Autodesk Fusion 360 part; units mm, degrees
(part 5 of 6)
sketch "Sketch1" plane through (0, 0, 0) normal (0, 1, 0) x (1, 0, 0)
  line L0 (-76.2, 57.15) -> (-76.2, -57.15) construction
  line L1 (76.2, -49.53) -> (76.2, 45.72) construction
  line L2 (-76.2, 57.15) -> (-38.1, 57.15) construction
  line L3 (-38.1, 57.15) -> (-38.1, 62.865) construction
  line L4 (-38.1, 62.865) -> (-19.05, 62.865) construction
  line L5 (-19.05, 62.865) -> (-19.05, 55.245) construction
  line L6 (-19.05, 55.245) -> (0, 55.245) construction
  line L7 (0, 55.245) -> (0, 45.72) construction
  line L8 (0, 45.72) -> (76.2, 45.72) construction
  line L9 (-76.2, -57.15) -> (-19.05, -57.15) construction
  line L10 (-19.05, -57.15) -> (-19.05, -59.055) construction
  line L11 (-19.05, -59.055) -> (0, -59.055) construction
  line L12 (0, -59.055) -> (0, -68.58) construction
  line L13 (0, -68.58) -> (57.15, -68.58) construction
  line L14 (57.15, -68.58) -> (57.15, -49.53) construction
  line L15 (57.15, -49.53) -> (76.2, -49.53) construction
  line L16 (-19.05, -59.055) -> (-19.05, -59.16) construction
  line L17 (-19.05, -59.16) -> (-19.115, -59.16) construction
  line L18 (-19.115, -59.16) -> (-19.2509, -58.6529) construction
  line L19 (-19.2509, -58.6529) -> (-18.7438, -58.517) construction
  line L20 (-18.7438, -58.517) -> (-37.1447, -63.4475) construction
  line L21 (-37.1447, -63.4475) -> (-32.2142, -81.8484) construction
  line L22 (-32.2142, -81.8484) -> (-13.8133, -76.9179) construction
  line L23 (-13.8133, -76.9179) -> (-18.7438, -58.517) construction
  line L24 (-37.1447, -63.4475) -> (-73.9464, -73.3085) construction
  line L25 (-73.9464, -73.3085) -> (-64.0854, -110.1103) construction
  line L26 (-64.0854, -110.1103) -> (-8.8828, -95.3188) construction
  line L27 (-8.8828, -95.3188) -> (-13.8133, -76.9179) construction
  line L28 (-76.2, 57.15) -> (-86.56, 57.15) construction
  line L29 (-86.56, 57.15) -> (-86.56, 59.625) construction
  line L30 (-76.2, -57.15) -> (-86.56, -57.15) construction
  line L31 (-86.56, -57.15) -> (-86.56, -59.625) construction
  line L32 (-73.9464, -73.3085) -> (-74.587, -70.9179) construction
  line L33 (-74.587, -70.9179) -> (-84.594, -73.5992) construction
  line L34 (-64.0854, -110.1103) -> (-63.4448, -112.501) construction
  line L35 (-63.4448, -112.501) -> (-73.4518, -115.1823) construction
  line L36 (-8.8828, -95.3188) -> (-8.2422, -97.7094) construction
  line L37 (-8.2422, -97.7094) -> (-5.8515, -97.0689) construction
  line L38 (0, -68.58) -> (-2.475, -68.58) construction
  line L39 (-2.475, -68.58) -> (-2.475, -71.055) construction
  line L40 (57.15, -68.58) -> (59.625, -68.58) construction
  line L41 (59.625, -68.58) -> (59.625, -71.055) construction
  line L42 (57.15, -49.53) -> (59.625, -49.53) construction
  line L43 (59.625, -49.53) -> (59.625, -52.005) construction
  line L44 (76.2, -49.53) -> (78.675, -49.53) construction
  line L45 (78.675, -49.53) -> (78.675, -52.005) construction
  line L46 (76.2, 45.72) -> (78.675, 45.72) construction
  line L47 (78.675, 45.72) -> (78.675, 48.195) construction
  line L48 (0, 45.72) -> (2.475, 45.72) construction
  line L49 (2.475, 45.72) -> (2.475, 48.195) construction
  line L50 (0, 55.245) -> (2.475, 55.245) construction
  line L51 (2.475, 55.245) -> (2.475, 57.72) construction
  line L52 (-19.05, 55.245) -> (-16.575, 55.245) construction
  line L53 (-16.575, 55.245) -> (-16.575, 57.72) construction
  line L54 (-19.05, 62.865) -> (-16.575, 62.865) construction
  line L55 (-16.575, 62.865) -> (-16.575, 65.34) construction
  line L56 (-38.1, 62.865) -> (-40.575, 62.865) construction
  line L57 (-40.575, 62.865) -> (-40.575, 65.34) construction
  line L58 (-38.1, 57.15) -> (-40.575, 57.15) construction
  line L59 (-40.575, 57.15) -> (-40.575, 59.625) construction
  line L60 (-84.594, -73.5992) -> (-73.4518, -115.1823)
  line L61 (-73.4518, -115.1823) -> (-5.8515, -97.0689)
  line L62 (-5.8515, -97.0689) -> (-2.475, -71.055)
  line L63 (-2.475, -71.055) -> (59.625, -71.055)
  line L64 (59.625, -71.055) -> (59.625, -52.005)
  line L65 (59.625, -52.005) -> (78.675, -52.005)
  line L66 (78.675, -52.005) -> (78.675, 48.195)
  line L67 (2.475, 48.195) -> (78.675, 48.195)
  line L68 (2.475, 57.72) -> (2.475, 48.195)
  line L69 (-16.575, 57.72) -> (2.475, 57.72)
  line L70 (-16.575, 65.34) -> (-16.575, 57.72)
  line L71 (-16.575, 65.34) -> (-40.575, 65.34)
  line L72 (-40.575, 65.34) -> (-40.575, 59.625)
  line L73 (-40.575, 59.625) -> (-86.56, 59.625)
  line L74 (-86.56, 59.625) -> (-86.56, -59.625)
  line L75 (-86.56, -59.625) -> (-84.594, -73.5992)
  line L76 (-94.4114, -75.5973) -> (-80.5229, -127.4298)
  line L77 (-80.5229, -127.4298) -> (3.2035, -104.9953)
  line L78 (3.2035, -104.9953) -> (6.3109, -81.055)
  line L79 (6.3109, -81.055) -> (69.625, -81.055)
  line L80 (69.625, -81.055) -> (69.625, -62.005)
  line L81 (69.625, -62.005) -> (88.675, -62.005)
  line L82 (88.675, -62.005) -> (88.675, 58.195)
  line L83 (12.475, 58.195) -> (88.675, 58.195)
  line L84 (12.475, 67.72) -> (12.475, 58.195)
  line L85 (-6.575, 67.72) -> (12.475, 67.72)
  line L86 (-6.575, 75.34) -> (-6.575, 67.72)
  line L87 (-6.575, 75.34) -> (-50.575, 75.34)
  line L88 (-50.575, 75.34) -> (-50.575, 69.625)
  line L89 (-50.575, 69.625) -> (-96.56, 69.625)
  line L90 (-96.56, 69.625) -> (-96.56, -60.325)
  line L91 (-96.56, -60.325) -> (-94.4114, -75.5973)
  line L92 (-82.1642, -73.1047) -> (-71.7017, -112.1511)
  line L93 (-71.7017, -112.1511) -> (-8.0926, -95.1071)
  line L94 (-8.0926, -95.1071) -> (-4.6495, -68.58)
  line L95 (-4.6495, -68.58) -> (57.15, -68.58)
  line L96 (57.15, -68.58) -> (57.15, -49.53)
  line L97 (57.15, -49.53) -> (76.2, -49.53)
  line L98 (76.2, -49.53) -> (76.2, 45.72)
  line L99 (0, 45.72) -> (76.2, 45.72)
  line L100 (0, 55.245) -> (0, 45.72)
  line L101 (-19.05, 55.245) -> (0, 55.245)
  line L102 (-19.05, 62.865) -> (-19.05, 55.245)
  line L103 (-19.05, 62.865) -> (-38.1, 62.865)
  line L104 (-38.1, 62.865) -> (-38.1, 57.15)
  line L105 (-38.1, 57.15) -> (-84.085, 57.15)
  line L106 (-84.085, 57.15) -> (-84.085, -59.4518)
  line L107 (-84.085, -59.4518) -> (-82.1642, -73.1047)
  dimension "d69" = 114.3
  dimension "d70" = 38.1
  dimension "d71" = 5.715
  dimension "d72" = 19.05
  dimension "d73" = 7.62
  dimension "d74" = 19.05
  dimension "d75" = 9.525
  dimension "d76" = 57.15
  dimension "d77" = 1.905
  dimension "d78" = 19.05
  dimension "d79" = 9.525
  dimension "d80" = 57.15
  dimension "d81" = 19.05
  dimension "d82" = 0.105
  dimension "d83" = 0.065
  dimension "d84" = 0.525
  dimension "d85" = 0.525
  dimension "d86" = 19.05
  dimension "d87" = 19.05
  dimension "d88" = 38.1
  dimension "d89" = 38.1
  dimension "d90" = 57.15
  dimension "d91" = 10.36
  dimension "d92" = 2.475
  dimension "d93" = 10.36
  dimension "d94" = 2.475
  dimension "d95" = 2.475
  dimension "d96" = 10.36
  dimension "d97" = 2.475
  dimension "d98" = 10.36
  dimension "d99" = 2.475
  dimension "d100" = 2.475
  dimension "d101" = 2.475
  dimension "d102" = 2.475
  dimension "d103" = 2.475
  dimension "d104" = 2.475
  dimension "d105" = 2.475
  dimension "d106" = 2.475
  dimension "d107" = 2.475
  dimension "d108" = 2.475
  dimension "d109" = 2.475
  dimension "d110" = 2.475
  dimension "d111" = 2.475
  dimension "d112" = 2.475
  dimension "d113" = 2.475
  dimension "d114" = 2.475
  dimension "d115" = 2.475
  dimension "d116" = 2.475
  dimension "d117" = 2.475
  dimension "d118" = 2.475
  dimension "d119" = 2.475
  dimension "d120" = 2.475
  dimension "d121" = 2.475
  dimension "d122" = 2.475
  dimension "d123" = 10
  constraint parallel L0 L1
  constraint perpendicular L3 L4
  constraint perpendicular L4 L5
  constraint perpendicular L3 L6
  constraint perpendicular L6 L7
  constraint perpendicular L1 L8
  constraint perpendicular L10 L11
  constraint perpendicular L12 L13
  constraint perpendicular L13 L14
  constraint perpendicular L1 L15
  constraint perpendicular L11 L16
  constraint perpendicular L18 L19
  constraint perpendicular L16 L17
  constraint collinear L19 L20
  constraint parallel L21 L23
  constraint parallel L20 L22
  constraint perpendicular L21 L22
  constraint perpendicular L21 L24
  constraint perpendicular L24 L25
  constraint perpendicular L25 L26
  constraint perpendicular L0 L28
  constraint perpendicular L28 L29
  constraint perpendicular L0 L30
  constraint perpendicular L9 L31
  constraint perpendicular L24 L32
  constraint perpendicular L25 L33
  constraint perpendicular L26 L34
  constraint perpendicular L25 L35
  constraint perpendicular L26 L36
  constraint perpendicular L27 L37
  constraint perpendicular L12 L38
  constraint perpendicular L38 L39
  constraint perpendicular L14 L40
  constraint perpendicular L13 L41
  constraint perpendicular L14 L42
  constraint perpendicular L42 L43
  constraint perpendicular L1 L44
  constraint perpendicular L15 L45
  constraint perpendicular L1 L46
  constraint perpendicular L8 L47
  constraint perpendicular L7 L48
  constraint perpendicular L8 L49
  constraint perpendicular L7 L50
  constraint perpendicular L6 L51
  constraint coincident L6 L52.end
  constraint perpendicular L52 L53
  constraint perpendicular L5 L54
  constraint perpendicular L4 L55
  constraint perpendicular L3 L56
  constraint perpendicular L56 L57
  constraint coincident L2 L58.end
  constraint perpendicular L3 L58
  constraint perpendicular L58 L59
  constraint perpendicular L45 L65
  constraint perpendicular L47 L67
  constraint perpendicular L73 L74
  measures "d69" distance of L0.start L0.end
  measures "d70" distance of L0.start L2.end
  measures "d71" distance of L2.end L3.end
  measures "d72" distance of L3.end L4.end
  measures "d73" distance of L4.end L5.end
  measures "d74" distance of L5.end L6.end
  measures "d75" distance of L6.end L7.end
  measures "d76" distance of L0.end L9.end
  measures "d77" distance of L9.end L10.end
  measures "d78" distance of L10.end L11.end
  measures "d79" distance of L11.end L12.end
  measures "d80" distance of L12.end L13.end
  measures "d81" distance of L13.end L14.end
  measures "d82" distance of L10.end L16.end
  measures "d83" distance of L16.end L17.end
  measures "d84" distance of L17.end L18.end
  measures "d85" distance of L18.end L19.end
  measures "d86" distance of L19.end L20.end
  measures "d87" distance of L19.end L22.end
  measures "d88" distance of L20.end L24.end
  measures "d89" distance of L24.end L25.end
  measures "d90" distance of L25.end L26.end
  measures "d91" distance of L0.start L28.end
  measures "d92" distance of L28.end L29.end
  measures "d93" distance of L0.end L30.end
  measures "d94" distance of L30.end L31.end
  measures "d95" distance of L24.end L32.end
  measures "d96" distance of L32.end L33.end
  measures "d97" distance of L25.end L34.end
  measures "d98" distance of L34.end L35.end
  measures "d99" distance of L26.end L36.end
  measures "d100" distance of L36.end L37.end
  measures "d101" distance of L12.end L38.end
  measures "d102" distance of L38.end L39.end
  measures "d103" distance of L13.end L40.end
  measures "d104" distance of L40.end L41.end
  measures "d105" distance of L14.end L42.end
  measures "d106" distance of L42.end L43.end
  measures "d107" distance of L1.start L44.end
  measures "d108" distance of L44.end L45.end
  measures "d109" distance of L1.end L46.end
  measures "d110" distance of L46.end L47.end
  measures "d111" distance of L7.end L48.end
  measures "d112" distance of L48.end L49.end
  measures "d113" distance of L6.end L50.end
  measures "d114" distance of L50.end L51.end
  measures "d115" distance of L5.end L52.end
  measures "d116" distance of L52.end L53.end
  measures "d117" distance of L4.end L54.end
  measures "d118" distance of L54.end L55.end
  measures "d119" distance of L3.end L56.end
  measures "d120" distance of L56.end L57.end
  measures "d121" distance of L2.end L58.end
  measures "d122" distance of L58.end L59.end
extrude "Extrude1" add sketch "Sketch1" against normal blind 24.3975 contours L60 L61 L62 L63 L64 L65 L66 L67 L68 L69 L70 L71 L72 L73 L74 L75 | L76 L77 L78 L79 L80 L81 L82 L83 L84 L85 L86 L87 L88 L89 L90 L91
extrude "Extrude2" cut sketch "Sketch1" against normal blind 4.05 contours L60 L61 L62 L63 L64 L65 L66 L67 L68 L69 L70 L71 L72 L73 L74 L75
sketch "Sketch2" plane through (0, 0, 0) normal (0, 1, 0) x (-1, 0, 0)
  line L0 (40.575, -59.625) -> (40.575, -65.34)
  line L1 (40.575, -65.34) -> (16.575, -65.34)
  line L2 (16.575, -65.34) -> (16.575, -57.72)
  line L3 (16.575, -57.72) -> (-2.475, -57.72)
  line L4 (-2.475, -57.72) -> (-2.475, -48.195)
  line L5 (-2.475, -48.195) -> (-78.675, -48.195)
  line L6 (-78.675, -48.195) -> (-78.675, 52.005)
  line L7 (-78.675, 52.005) -> (-59.625, 52.005)
  line L8 (-59.625, 52.005) -> (-59.625, 71.055)
  line L9 (-59.625, 71.055) -> (2.475, 71.055)
  line L10 (2.475, 71.055) -> (5.8515, 97.0689)
  line L11 (5.8515, 97.0689) -> (73.4518, 115.1823)
  line L12 (73.4518, 115.1823) -> (84.594, 73.5992)
  line L13 (84.594, 73.5992) -> (86.56, 59.625)
  line L14 (86.56, 59.625) -> (86.56, -59.625)
  line L15 (86.56, -59.625) -> (40.575, -59.625)
  line L16 (6.575, -75.34) -> (50.575, -75.34)
  line L17 (50.575, -75.34) -> (50.575, -69.625)
  line L18 (50.575, -69.625) -> (96.56, -69.625)
  line L19 (96.56, -69.625) -> (96.56, 60.325)
  line L20 (96.56, 60.325) -> (94.4114, 75.5973)
  line L21 (94.4114, 75.5973) -> (80.5229, 127.4298)
  line L22 (80.5229, 127.4298) -> (-3.2035, 104.9953)
  line L23 (-3.2035, 104.9953) -> (-6.3109, 81.055)
  line L24 (-6.3109, 81.055) -> (-69.625, 81.055)
  line L25 (-69.625, 81.055) -> (-69.625, 62.005)
  line L26 (-69.625, 62.005) -> (-88.675, 62.005)
  line L27 (-88.675, 62.005) -> (-88.675, -58.195)
  line L28 (-88.675, -58.195) -> (-12.475, -58.195)
  line L29 (-12.475, -58.195) -> (-12.475, -67.72)
  line L30 (-12.475, -67.72) -> (6.575, -67.72)
  line L31 (6.575, -67.72) -> (6.575, -75.34)
  line L32 (73.4518, 115.1823) -> (76.04, 105.5231) construction
  line L33 (76.04, 105.5231) -> (85.6993, 108.1113)
  line L34 (73.4518, 115.1823) -> (63.7926, 112.5941) construction
  line L35 (63.7926, 112.5941) -> (61.2044, 122.2534)
  line L36 (-78.675, 52.005) -> (-88.675, 52.005)
  line L37 (-59.625, 71.055) -> (-59.625, 81.055)
  line L38 (-78.675, -48.195) -> (-68.675, -48.195) construction
  line L39 (-68.675, -48.195) -> (-68.675, -58.195)
  line L40 (-78.675, -48.195) -> (-78.675, -38.195) construction
  line L41 (-78.675, -38.195) -> (-88.675, -38.195)
  line L42 (86.56, -59.625) -> (76.56, -59.625) construction
  line L43 (86.56, -59.625) -> (86.56, -49.625) construction
  line L44 (86.56, -49.625) -> (96.56, -49.625)
  line L45 (76.56, -59.625) -> (76.56, -69.625)
  line L46 (-83.675, -38.195) -> (-83.675, 52.005) construction
  line L47 (-83.675, -38.195) -> (-139.0653, 58.6159) construction
  circle A0 centre (-83.675, -38.195) radius 30 construction
  circle A1 centre (-98.5733, -12.1558) radius 30 construction
  circle A2 centre (-113.4716, 13.8834) radius 30 construction
  circle A3 centre (-128.3699, 39.9226) radius 30 construction
  line L48 (-128.3699, 39.9226) -> (-83.675, 52.005) construction
  line L49 (-113.4716, 13.8834) -> (-99.4095, 47.7515) construction
  circle A4 centre (-98.5733, -12.1558) radius 36.6714 construction
  circle A5 centre (-83.675, -38.195) radius 36.6714 construction
  line L50 (-83.675, -38.195) -> (-118.1158, -50.7895) construction
  line L51 (-98.5733, -12.1558) -> (-133.0141, -24.7503) construction
  line L52 (-98.5733, -12.1558) -> (-69.6128, -4.3269) construction
  line L53 (-113.4716, 13.8834) -> (-84.5112, 21.7123) construction
  line L54 (-84.5112, 21.7123) -> (-74.4436, 24.4339) construction
  circle A6 centre (-83.675, 21.9383) radius 1.275
  circle A7 centre (-83.675, -8.1283) radius 1.275
  line L55 (-59.625, 52.005) -> (-69.625, 62.005) construction
  line L56 (5.8515, 97.0689) -> (-3.2035, 104.9953) construction
  line L57 (5.8515, 97.0689) -> (34.8293, 104.8334) construction
  line L58 (34.8293, 104.8334) -> (32.2411, 114.4927) construction
  line L59 (2.475, 71.055) -> (-6.3109, 81.055) construction
  line L60 (4.1633, 84.0619) -> (-4.7572, 93.0252) construction
  line L61 (-0.297, 88.5436) -> (33.5352, 109.6631) construction
  line L62 (16.6191, 99.1033) -> (-3.2035, 104.9953) construction
  line L63 (6.7078, 102.0493) -> (1.324, 101.0321) construction
  line L64 (6.7078, 102.0493) -> (3.868, 98.8052) construction
  line L65 (3.868, 98.8052) -> (1.324, 101.0321) construction
  circle A8 centre (2.596, 99.9186) radius 1.275
  line L66 (-1.918, 76.055) -> (-59.625, 76.055) construction
  circle A9 centre (-30.7715, 76.055) radius 1.275
  line L67 (84.594, 73.5992) -> (94.2533, 76.1874) construction
  line L68 (89.4236, 74.8933) -> (80.8697, 106.8172) construction
  circle A10 centre (85.1466, 90.8552) radius 1.275
  line L69 (86.56, 59.625) -> (96.56, 59.625) construction
  line L70 (91.56, 59.625) -> (91.56, -49.625) construction
  line L71 (91.56, -49.625) -> (139.6006, 64.0625) construction
  circle A11 centre (91.56, -49.625) radius 30 construction
  circle A12 centre (103.2373, -21.9909) radius 30 construction
  circle A13 centre (114.9145, 5.6431) radius 30 construction
  circle A14 centre (126.5918, 33.2772) radius 30 construction
  line L72 (126.5918, 33.2772) -> (91.56, 59.625) construction
  line L73 (114.9145, 5.6431) -> (102.6161, 51.3096) construction
  circle A15 centre (103.2373, -21.9909) radius 47.2935 construction
  circle A16 centre (91.56, -49.625) radius 47.2935 construction
  line L74 (91.56, -49.625) -> (137.2904, -61.6834) construction
  line L75 (103.2373, -21.9909) -> (148.9677, -34.0493) construction
  line L76 (103.2373, -21.9909) -> (79.2616, -3.9585) construction
  line L77 (114.9145, 5.6431) -> (90.9388, 23.6755) construction
  circle A17 centre (91.56, 23.2083) radius 1.275
  circle A18 centre (91.56, -13.2083) radius 1.275
  line L78 (-12.475, -58.195) -> (-2.475, -48.195) construction
  line L79 (-7.475, -53.195) -> (-68.675, -53.195) construction
  line L80 (28.575, -75.34) -> (28.575, -65.34) construction
  circle A19 centre (28.575, -70.34) radius 1.275
  circle A20 centre (-38.075, -53.195) radius 1.275
  line L81 (73.4518, 115.1823) -> (80.5229, 127.4298) construction
  circle A21 centre (80.5229, 127.4298) radius 8.75 construction
  line L82 (86.56, -59.625) -> (96.56, -69.625) construction
  circle A22 centre (96.56, -69.625) radius 8.75 construction
  line L83 (-78.675, -48.195) -> (-88.675, -58.195) construction
  circle A23 centre (-88.675, -58.195) radius 8.75 construction
  circle A24 centre (-69.625, 62.005) radius 6.25 construction
  circle A25 centre (-65.2056, 57.5856) radius 1.025
  circle A26 centre (-82.4878, -52.0078) radius 1.025
  circle A27 centre (90.3728, -63.4378) radius 1.025
  circle A28 centre (76.1479, 119.852) radius 1.025
  dimension "d129" = 10
  dimension "d130" = 10
  dimension "d131" = 10
  dimension "d132" = 10
  dimension "d133" = 10
  dimension "d134" = 10
  dimension "d135" = 60
  dimension "d136" = 2.55
  dimension "d137" = 2.55
  dimension "d138" = 30
  dimension "d139" = 2.55
  dimension "d140" = 2.55
  dimension "d141" = 2.55
  dimension "d142" = 60
  dimension "d143" = 2.55
  dimension "d144" = 2.55
  dimension "d145" = 2.55
  dimension "d146" = 2.55
  dimension "d147" = 17.5
  dimension "d148" = 17.5
  dimension "d149" = 17.5
  dimension "d150" = 12.5
  dimension "d151" = 2.05
  dimension "d152" = 2.05
  dimension "d153" = 2.05
  dimension "d154" = 2.05
  constraint coincident L11.end L12.start
  constraint coincident L12 L32.end
  constraint coincident L21 L33.end
  constraint perpendicular L21 L33
  constraint coincident L11 L34.end
  constraint coincident L22 L35.end
  constraint perpendicular L22 L35
  constraint coincident L6.end L7.start
  constraint coincident L27 L36.end
  constraint perpendicular L27 L36
  constraint coincident L8.end L9.start
  constraint coincident L24 L37.end
  constraint perpendicular L24 L37
  constraint coincident L5.end L6.start
  constraint coincident L5 L38.end
  constraint coincident L28 L39.end
  constraint perpendicular L28 L39
  constraint coincident L6 L40.end
  constraint coincident L27 L41.end
  constraint perpendicular L27 L41
  constraint coincident L14.end L15.start
  constraint coincident L15 L42.end
  constraint coincident L14 L43.end
  constraint coincident L19 L44.end
  constraint perpendicular L19 L44
  constraint coincident L18 L45.end
  constraint perpendicular L18 L45
  constraint midpoint L41 L46.start
  constraint midpoint L36 L46.end
  constraint coincident L46.start L47.start
  constraint coincident A0 A1.centre
  constraint coincident L47 A1.centre
  constraint coincident L46.start A1
  constraint coincident A1 A2.centre
  constraint coincident L47 A2.centre
  constraint coincident A1.centre A2
  constraint coincident A2 A3.centre
  constraint coincident L47 A3.centre
  constraint coincident A2.centre A3
  constraint coincident A3.centre L48.start
  constraint coincident A2.centre L49.start
  constraint coincident L48 L49.end
  constraint coincident A3 L49.end
  constraint concentric A1 A4
  constraint concentric A0 A5
  constraint coincident A5 L50.end
  constraint coincident A1.centre A4.centre
  constraint coincident A4 L51.end
  constraint parallel L50 L51
  constraint equal L49 L51
  constraint equal L49 L50
  constraint coincident A5 L52.end
  constraint coincident A1 L52.end
  constraint coincident A4 L53.end
  constraint coincident A2 L53.end
  constraint perpendicular A2 L54
  constraint coincident L54 A6.centre
  constraint coincident L46 A6.centre
  constraint coincident L46 A7.centre
  constraint coincident L52 A7.centre
  constraint coincident L7.end L8.start
  constraint coincident L25.end L26.start
  constraint coincident L10.end L11.start
  constraint coincident L22.end L23.start
  constraint parallel L11 L57
  constraint coincident L22 L58.end
  constraint perpendicular L22 L58
  constraint coincident L9.end L10.start
  constraint coincident L23.end L24.start
  constraint midpoint L10 L60.start
  constraint midpoint L23 L60.end
  constraint midpoint L60 L61.start
  constraint midpoint L58 L61.end
  constraint midpoint L61 L62.start
  constraint midpoint L62 L63.start
  constraint midpoint L56 L63.end
  constraint coincident L56 L64.end
  constraint perpendicular L56 L64
  constraint midpoint L65 A8.centre
  constraint midpoint L59 L66.start
  constraint midpoint L37 L66.end
  constraint midpoint L66 A9.centre
  constraint coincident L12.end L13.start
  constraint coincident L21 L67.end
  constraint perpendicular L21 L67
  constraint midpoint L67 L68.start
  constraint midpoint L33 L68.end
  constraint midpoint L68 A10.centre
  constraint coincident L13.end L14.start
  constraint coincident L19 L69.end
  constraint perpendicular L19 L69
  constraint midpoint L69 L70.start
  constraint midpoint L44 L70.end
  constraint coincident L70.end L71.start
  constraint coincident A11 A12.centre
  constraint coincident L71 A12.centre
  constraint coincident L70.end A12
  constraint coincident A12 A13.centre
  constraint coincident L71 A13.centre
  constraint coincident A12.centre A13
  constraint coincident A13 A14.centre
  constraint coincident L71 A14.centre
  constraint coincident A13.centre A14
  constraint coincident A14.centre L72.start
  constraint coincident A13.centre L73.start
  constraint coincident A14 L73.end
  constraint coincident L72 L73.end
  constraint concentric A12 A15
  constraint coincident A16 L74.end
  constraint coincident A12.centre A15.centre
  constraint coincident A15 L75.end
  constraint parallel L74 L75
  constraint equal L73 L74
  constraint equal L73 L75
  constraint coincident A12 L76.end
  constraint coincident A16 L76.end
  constraint coincident A13 L77.end
  constraint coincident A15 L77.end
  constraint coincident L77 A17.centre
  constraint coincident L70 A17.centre
  constraint coincident L76 A18.centre
  constraint coincident L70 A18.centre
  constraint coincident L28.end L29.start
  constraint coincident L4.end L5.start
  constraint midpoint L78 L79.start
  constraint midpoint L39 L79.end
  constraint midpoint L16 L80.start
  constraint midpoint L1 L80.end
  constraint midpoint L80 A19.centre
  constraint midpoint L79 A20.centre
  constraint coincident L21.end L22.start
  constraint coincident L18.end L19.start
  constraint coincident L27.end L28.start
  constraint coincident A24 A25.centre
  constraint coincident L55 A25.centre
  constraint coincident L83 A26.centre
  constraint coincident A23 A26.centre
  constraint coincident L82 A27.centre
  constraint coincident A22 A27.centre
  constraint coincident A21 A28.centre
  constraint coincident L81 A28.centre
  measures "d129" distance of L11.end L32.end
  measures "d130" distance of L11.end L34.end
  measures "d131" distance of L5.end L38.end
  measures "d132" distance of L5.end L40.end
  measures "d133" distance of L14.end L42.end
  measures "d134" distance of L14.end L43.end
  measures "d135" diameter of A0
  measures "d136" diameter of A6
  measures "d137" diameter of A7
  measures "d138" distance of L10.end L57.end
  measures "d139" diameter of A8
  measures "d140" diameter of A9
  measures "d141" diameter of A10
  measures "d142" diameter of A11
  measures "d143" diameter of A17
  measures "d144" diameter of A18
  measures "d145" diameter of A19
  measures "d146" diameter of A20
  measures "d147" diameter of A21
  measures "d148" diameter of A22
  measures "d149" diameter of A23
  measures "d150" diameter of A24
  measures "d151" diameter of A25
  measures "d152" diameter of A26
  measures "d153" diameter of A27
  measures "d154" diameter of A28
extrude "Extrude3" cut sketch "Sketch2" against normal blind 4.95 contours A6 | A7 | A8 | A9 | A10 | A17 | A18 | A19 | A20
fillet "Fillet1" radius 1.275 9 edges at (-1.4073, -4.95, 100.3797) (31.9602, -4.95, 76.5161) (84.8637, -4.95, 22.3994) (84.8637, -4.95, -7.6673) (39.2637, -4.95, -52.7339) (-27.3863, -4.95, -69.8789) (-90.3713, -4.95, -12.7473) (-90.3713, -4.95, 23.6694) (-83.9579, -4.95, 91.3163)
extrude "Extrude4" cut sketch "Sketch2" against normal through all contours A25 | A26 | A27 | A28
extrude "Extrude5" cut sketch "Sketch2" against normal blind 3.2 contours L14 L15 L18 L19 L44 L45 | L5 L6 L27 L28 L39 L41 | L11 L12 L21 L22 L33 L35 | L7 L8 L24 L25 L26 L27 L36 L37
sketch "Sketch3" plane through (-84.085, 0, 0) normal (1, 0, 0) x (0, 0, -1)
  line L0 (57.15, -4.05) -> (-59.4518, -4.05)
  line L1 (-59.4518, -4.05) -> (-59.4518, -24.3975)
  line L2 (-59.4518, -24.3975) -> (57.15, -24.3975)
  line L3 (57.15, -24.3975) -> (57.15, -4.05)
  line L4 (57.15, -4.05) -> (-47.1, -4.05) construction
  line L5 (-47.1, -4.05) -> (-47.1, -6.961) construction
  line L6 (-42.93, -5.681) -> (-51.27, -5.681) construction
  line L7 (-51.27, -5.681) -> (-51.27, -8.241) construction
  line L8 (-51.27, -8.241) -> (-42.93, -8.241) construction
  line L9 (-42.93, -8.241) -> (-42.93, -5.681) construction
  line L10 (-42.93, -5.681) -> (-51.27, -8.241) construction
  line L11 (-51.27, -5.681) -> (-42.93, -8.241) construction
  line L12 (-41.1, -4.711) -> (-53.1, -4.711)
  line L13 (-53.1, -4.711) -> (-53.1, -9.211)
  line L14 (-53.1, -9.211) -> (-41.1, -9.211)
  line L15 (-41.1, -9.211) -> (-41.1, -4.711)
  line L16 (-41.1, -4.711) -> (-53.1, -9.211) construction
  line L17 (-53.1, -4.711) -> (-41.1, -9.211) construction
  line L18 (57.15, -4.05) -> (32.15, -4.05) construction
  line L19 (-47.1, -4.05) -> (-56.35, -4.05) construction
  line L20 (-56.35, -4.05) -> (-37.85, -4.05)
  line L21 (-37.85, -4.05) -> (-37.85, -10.441)
  line L22 (-37.85, -10.441) -> (-56.35, -10.441)
  line L23 (-56.35, -10.441) -> (-56.35, -4.05)
  line L24 (32.15, -4.05) -> (32.15, -5.95) construction
  line L25 (32.15, -5.95) -> (29.65, -5.95)
  line L26 (29.65, -5.95) -> (29.65, -13.45)
  line L27 (29.65, -13.45) -> (32.15, -13.45)
  line L28 (32.15, -13.45) -> (32.15, -5.95)
  line L29 (29.65, -5.95) -> (-20.85, -5.95)
  line L30 (-20.85, -5.95) -> (-20.85, -10.95)
  line L31 (-20.85, -10.95) -> (29.65, -10.95)
  line L32 (29.65, -10.95) -> (29.65, -5.95)
  line L33 (-20.85, -5.95) -> (-23.35, -5.95)
  line L34 (-23.35, -5.95) -> (-23.35, -13.45)
  line L35 (-23.35, -13.45) -> (-20.85, -13.45)
  line L36 (-20.85, -13.45) -> (-20.85, -5.95)
  point P0 (-47.1, -6.961)
  point P1 (-47.1, -6.961)
  point P2 (-47.1, -6.961)
  dimension "d162" = 104.25
  dimension "d163" = 2.911
  dimension "d164" = 8.34
  dimension "d165" = 2.56
  dimension "d166" = 12
  dimension "d167" = 4.5
  dimension "d168" = 25
  dimension "d187" = 9.25
  dimension "d188" = 18.5
  dimension "d189" = 6.391
  dimension "d230" = 1.9
  dimension "d231" = 2.5
  dimension "d232" = 7.5
  dimension "d233" = 50.5
  dimension "d234" = 5
  dimension "d235" = 2.5
  dimension "d236" = 7.5
  constraint coincident L0.start L3.end
  constraint coincident L0 L4.end
  constraint perpendicular L0 L5
  constraint horizontal L6
  constraint perpendicular L6 L7
  constraint parallel L6 L8
  constraint parallel L7 L9
  constraint coincident L10 P2
  constraint coincident L11 P2
  constraint coincident P2 P1
  constraint horizontal L12
  constraint perpendicular L12 L13
  constraint parallel L12 L14
  constraint parallel L13 L15
  constraint coincident L16 P2
  constraint coincident L17 P2
  constraint coincident L4 L18.end
  constraint coincident L0 L19.end
  constraint horizontal L20
  constraint vertical L21
  constraint horizontal L22
  constraint vertical L23
  constraint perpendicular L18 L24
  constraint horizontal L25
  constraint vertical L26
  constraint horizontal L27
  constraint vertical L28
  constraint horizontal L29
  constraint vertical L30
  constraint horizontal L31
  constraint vertical L32
  constraint horizontal L33
  constraint vertical L34
  constraint horizontal L35
  constraint vertical L36
  measures "d162" distance of L0.start L4.end
  measures "d163" distance of L4.end P2
  measures "d164" distance of L7.end L8.end
  measures "d165" distance of L6.end L7.end
  measures "d166" distance of L13.end L14.end
  measures "d167" distance of L12.end L13.end
  measures "d168" distance of L0.start L18.end
  measures "d187" distance of L4.end L19.end
  measures "d188" distance of L19.end L20.end
  measures "d189" distance of L19.end L22.end
  measures "d230" distance of L18.end L24.end
  measures "d231" distance of L24.end L25.end
  measures "d232" distance of L24.end L27.end
  measures "d233" distance of L25.end L29.end
  measures "d234" distance of L25.end L31.end
  measures "d235" distance of L29.end L33.end
  measures "d236" distance of L29.end L35.end
extrude "Extrude6" cut sketch "Sketch3" against normal through all contours L12 L13 L14 L15
extrude "Extrude7" add sketch "Sketch3" along normal blind 2.5 contours L26 L29 L30 L31 L32 L36
extrude "Extrude8" add sketch "Sketch3" along normal blind 39 contours L25 L26 L27 L28 L32 | L30 L33 L34 L35 L36
sketch "Sketch11" plane through (0, 0, 23.35) normal (0, 0, 1) x (1, 0, 0)
  line L0 (-84.085, -5.95) -> (-84.085, -13.45)
  line L1 (-84.085, -13.45) -> (-45.085, -13.45)
  line L2 (-45.085, -13.45) -> (-45.085, -5.95)
  line L3 (-45.085, -5.95) -> (-84.085, -5.95)
  line L4 (-64.585, -13.45) -> (-64.585, -5.95) construction
  line L5 (-64.585, -9.7) -> (-45.085, -9.7)
  line L6 (-64.585, -9.7) -> (-64.585, -13.45)
  constraint midpoint L1 L4.start
  constraint midpoint L3 L4.end
  constraint midpoint L4 L5.start
  constraint midpoint L2 L5.end
extrude "Extrude9" cut sketch "Sketch11" against normal blind 1.25 contours L1 L2 L5 L6
sketch "Sketch12" plane through (0, 0, -32.15) normal (0, 0, -1) x (-1, 0, 0)
  line L0 (84.085, -13.45) -> (84.085, -5.95)
  line L1 (84.085, -5.95) -> (45.085, -5.95)
  line L2 (45.085, -5.95) -> (45.085, -13.45)
  line L3 (45.085, -13.45) -> (84.085, -13.45)
  line L4 (64.585, -13.45) -> (64.585, -5.95) construction
  line L5 (64.585, -9.7) -> (45.085, -9.7)
  line L6 (64.585, -9.7) -> (64.585, -13.45)
  constraint midpoint L3 L4.start
  constraint midpoint L1 L4.end
  constraint midpoint L4 L5.start
  constraint midpoint L2 L5.end
extrude "Extrude10" cut sketch "Sketch12" against normal blind 1.25 contours L2 L3 L5 L6
extrude "Extrude12" cut sketch "Sketch3" against normal blind 2.475 contours L0 L20 L21 L22 L23
sketch "Sketch6" plane through (0, -4.05, 0) normal (0, 1, 0) x (-1, 0, 0)
  line L0 (84.085, 56.35) -> (86.56, 56.35)
  line L1 (86.56, 56.35) -> (86.56, 59.625)
  line L2 (86.56, 59.625) -> (84.594, 73.5992)
  line L3 (84.594, 73.5992) -> (73.4518, 115.1823)
  line L4 (73.4518, 115.1823) -> (5.8515, 97.0689)
  line L5 (5.8515, 97.0689) -> (2.475, 71.055)
  line L6 (2.475, 71.055) -> (-59.625, 71.055)
  line L7 (-59.625, 71.055) -> (-59.625, 52.005)
  line L8 (-59.625, 52.005) -> (-78.675, 52.005)
  line L9 (-78.675, 52.005) -> (-78.675, -48.195)
  line L10 (-78.675, -48.195) -> (-2.475, -48.195)
  line L11 (-2.475, -48.195) -> (-2.475, -57.72)
  line L12 (-2.475, -57.72) -> (16.575, -57.72)
  line L13 (16.575, -57.72) -> (16.575, -65.34)
  line L14 (16.575, -65.34) -> (40.575, -65.34)
  line L15 (40.575, -65.34) -> (40.575, -59.625)
  line L16 (40.575, -59.625) -> (86.56, -59.625)
  line L17 (86.56, 37.85) -> (84.085, 37.85)
  line L18 (84.085, -57.15) -> (38.1, -57.15)
  line L19 (38.1, -57.15) -> (38.1, -62.865)
  line L20 (38.1, -62.865) -> (19.05, -62.865)
  line L21 (19.05, -62.865) -> (19.05, -55.245)
  line L22 (19.05, -55.245) -> (0, -55.245)
  line L23 (0, -55.245) -> (0, -45.72)
  line L24 (0, -45.72) -> (-76.2, -45.72)
  line L25 (-76.2, -45.72) -> (-76.2, 49.53)
  line L26 (-76.2, 49.53) -> (-57.15, 49.53)
  line L27 (-57.15, 49.53) -> (-57.15, 68.58)
  line L28 (-57.15, 68.58) -> (4.6495, 68.58)
  line L29 (4.6495, 68.58) -> (8.0926, 95.1071)
  line L30 (8.0926, 95.1071) -> (71.7017, 112.1511)
  line L31 (71.7017, 112.1511) -> (82.1642, 73.1047)
  line L32 (82.1642, 73.1047) -> (84.085, 59.4518)
  line L33 (84.085, -57.15) -> (84.085, 47.625) construction
  line L34 (84.085, 47.625) -> (83.5096, 47.625) construction
  line L35 (83.5096, 47.625) -> (83.5096, 64.735) construction
  line L36 (83.5096, 64.735) -> (84.16, 60.8896) construction
  line L37 (83.5096, 64.735) -> (82.8592, 68.5804) construction
  line L38 (82.8592, 68.5804) -> (85.2527, 68.9171) construction
  line L39 (84.16, 60.8896) -> (86.339, 61.1961) construction
  line L40 (86.339, 61.1961) -> (85.2527, 68.9171)
  line L41 (85.2527, 68.9171) -> (80.3015, 68.2205)
  line L42 (86.339, 61.1961) -> (81.3877, 60.4996)
  line L43 (81.3877, 60.4996) -> (80.3015, 68.2205)
  line L44 (86.56, -59.625) -> (86.56, 37.85)
  line L45 (84.085, 37.85) -> (84.085, -57.15)
  line L46 (84.085, 59.4518) -> (84.085, 56.35)
  dimension "d192" = 104.775
  dimension "d193" = 0.5754
  dimension "d194" = 17.11
  dimension "d196" = 3.9
  dimension "d197" = 3.9
  dimension "d198" = 5
  dimension "d199" = 5
  constraint coincident L18.start L33.start
  constraint perpendicular L18 L33
  constraint perpendicular L33 L34
  constraint perpendicular L34 L35
  constraint parallel L36 L37
  constraint coincident L2 L38.end
  constraint perpendicular L2 L38
  constraint coincident L2 L39.end
  constraint perpendicular L2 L39
  constraint perpendicular L2 L41
  constraint perpendicular L2 L42
  measures "d192" distance of L18.start L33.end
  measures "d193" distance of L33.end L34.end
  measures "d194" distance of L34.end L35.end
  measures "d196" distance of L35.end L36.end
  measures "d197" distance of L35.end L37.end
  measures "d198" distance of L38.end L41.end
  measures "d199" distance of L39.end L42.end
extrude "Extrude13" cut sketch "Sketch6" against normal blind 1.65 contours L2 L32 L40 L41 L42
sketch "Sketch7" plane through (-93.1057, 0, 13.0988) normal (0.990248, 0, -0.139316) x (-0.139316, 0, -0.990248)
  line L0 (-46.9844, 0) -> (-61.0962, 0)
  line L1 (-61.0962, 0) -> (-61.0962, -4.05)
  line L2 (-56.368, -5.7) -> (-48.571, -5.7)
  line L3 (-48.571, -5.7) -> (-48.571, -4.05)
  line L4 (-61.0962, -4.05) -> (-56.368, -4.05)
  line L5 (-46.9844, -4.05) -> (-46.9844, 0)
  line L6 (-56.368, -4.05) -> (-56.368, -3.55) construction
  line L7 (-56.368, -3.55) -> (-48.571, -3.55)
  line L8 (-48.571, -3.55) -> (-48.571, -5.7)
  line L9 (-48.571, -5.7) -> (-56.368, -5.7)
  line L10 (-56.368, -5.7) -> (-56.368, -3.55)
  line L11 (-56.368, -4.05) -> (-56.368, -5.7)
  line L12 (-48.571, -4.05) -> (-46.9844, -4.05)
  dimension "d202" = 0.5
  constraint horizontal L7
  constraint vertical L8
  constraint horizontal L9
  constraint vertical L10
  constraint coincident L2.end L3.start
  measures "d202" distance of L4.end L6.end
extrude "Extrude14" cut sketch "Sketch7" against normal through all contours L2 L3 L7 L8 L9 L10 L11
fillet "Fillet2" radius 0.25 12 edges at (-91.56, -9.211, 53.1) (-85.3225, -10.441, 56.35) (-85.3225, -4.05, 56.35) (-91.56, -4.711, 53.1) (-91.56, -9.211, 41.1) (-91.56, -4.711, 41.1) (-85.3225, -4.05, 37.85) (-85.3225, -10.441, 37.85) (-88.9785, -5.7, 69.4413) (-90.204, -3.55, 69.6137) (-91.2902, -3.55, 61.8927) (-90.0648, -5.7, 61.7203)
sketch "Sketch8" plane through (0, -24.3975, 0) normal (0, -1, 0) x (1, 0, 0)
  line L0 (-50.575, -75.34) -> (-6.575, -75.34)
  line L1 (-6.575, -75.34) -> (-6.575, -67.72)
  line L2 (-6.575, -67.72) -> (12.475, -67.72)
  line L3 (12.475, -67.72) -> (12.475, -58.195)
  line L4 (12.475, -58.195) -> (88.675, -58.195)
  line L5 (88.675, -58.195) -> (88.675, 62.005)
  line L6 (88.675, 62.005) -> (69.625, 62.005)
  line L7 (69.625, 62.005) -> (69.625, 81.055)
  line L8 (69.625, 81.055) -> (6.3109, 81.055)
  line L9 (6.3109, 81.055) -> (3.2035, 104.9953)
  line L10 (3.2035, 104.9953) -> (-80.5229, 127.4298)
  line L11 (-80.5229, 127.4298) -> (-94.4114, 75.5973)
  line L12 (-94.4114, 75.5973) -> (-96.56, 60.325)
  line L13 (-96.56, 60.325) -> (-96.56, -69.625)
  line L14 (-96.56, -69.625) -> (-50.575, -69.625)
  line L15 (-50.575, -69.625) -> (-50.575, -75.34)
  line L16 (-19.05, -62.865) -> (-38.1, -62.865)
  line L17 (-38.1, -62.865) -> (-38.1, -57.15)
  line L18 (-38.1, -57.15) -> (-84.085, -57.15)
  line L19 (-84.085, 59.4518) -> (-82.1642, 73.1047)
  line L20 (-82.1642, 73.1047) -> (-71.7017, 112.1511)
  line L21 (-71.7017, 112.1511) -> (-8.0926, 95.1071)
  line L22 (-8.0926, 95.1071) -> (-4.6495, 68.58)
  line L23 (-4.6495, 68.58) -> (57.15, 68.58)
  line L24 (57.15, 68.58) -> (57.15, 49.53)
  line L25 (57.15, 49.53) -> (76.2, 49.53)
  line L26 (76.2, 49.53) -> (76.2, -45.72)
  line L27 (76.2, -45.72) -> (0, -45.72)
  line L28 (0, -45.72) -> (0, -55.245)
  line L29 (0, -55.245) -> (-19.05, -55.245)
  line L30 (-19.05, -55.245) -> (-19.05, -62.865)
  circle A0 centre (82.4878, -52.0078) radius 1.025
  circle A1 centre (-76.1479, 119.852) radius 1.025
  circle A2 centre (-90.3728, -63.4378) radius 1.025
  circle A3 centre (65.2056, 57.5856) radius 1.025
  line L31 (76.2, -45.72) -> (76.2, -35.72) construction
  line L32 (76.2, -35.72) -> (88.675, -35.72)
  line L33 (-84.085, -57.15) -> (-84.085, -47.15) construction
  line L34 (-84.085, -47.15) -> (-96.56, -47.15)
  line L35 (76.2, 49.53) -> (76.2, 39.53) construction
  line L36 (76.2, 39.53) -> (88.675, 39.53)
  line L37 (-71.7017, 112.1511) -> (-74.2899, 102.4918) construction
  line L38 (-74.2899, 102.4918) -> (-86.3399, 105.7206)
  line L39 (-84.085, -57.15) -> (-84.085, 59.4518)
  dimension "d206" = 10
  dimension "d207" = 10
  dimension "d208" = 10
  dimension "d209" = 10
  constraint coincident L26.end L27.start
  constraint coincident L26 L31.end
  constraint coincident L5 L32.end
  constraint perpendicular L5 L32
  constraint coincident L18.end L33.start
  constraint perpendicular L18 L33
  constraint coincident L13 L34.end
  constraint perpendicular L13 L34
  constraint coincident L25.end L26.start
  constraint perpendicular L25 L35
  constraint coincident L5 L36.end
  constraint perpendicular L5 L36
  constraint coincident L20.end L21.start
  constraint coincident L20 L37.end
  constraint coincident L11 L38.end
  constraint perpendicular L11 L38
  measures "d206" distance of L26.end L31.end
  measures "d207" distance of L18.end L33.end
  measures "d208" distance of L25.end L35.end
  measures "d209" distance of L20.end L37.end
draft "Draft1" angle -2.75 neutral plane through (-96.56, 0, -69.625) pull (-1, 0, 0) 1 faces at (29.5583, -24.3975, -49.8783)
extrude "Extrude15" cut sketch "Sketch8" against normal blind 11.8975 contours L0 L1 L2 L3 L4 L5 L13 L14 L15 L16 L17 L18 L26 L27 L28 L29 L30 L32 L34 L39 | L5 L6 L7 L8 L9 L10 L11 L20 L21 L22 L23 L24 L25 L26 L36 L38
sketch "Sketch9" plane through (0, -12.5, 0) normal (0, -1, 0) x (1, 0, 0)
  circle A0 centre (-90.3728, -63.4378) radius 1.025
  circle A1 centre (82.4878, -52.0078) radius 1.025
  line L0 (76.2, -35.72) -> (76.2, -45.72)
  line L1 (76.2, -45.72) -> (0, -45.72)
  line L2 (0, -45.72) -> (0, -55.245)
  line L3 (0, -55.245) -> (-19.05, -55.245)
  line L4 (-19.05, -55.245) -> (-19.05, -62.865)
  line L5 (-19.05, -62.865) -> (-38.1, -62.865)
  line L6 (-38.1, -62.865) -> (-38.1, -57.15)
  line L7 (-38.1, -57.15) -> (-84.085, -57.15)
  line L8 (-84.085, -47.15) -> (-96.56, -47.15)
  line L9 (-96.56, -47.15) -> (-96.56, -69.625)
  line L10 (-96.56, -69.625) -> (-50.575, -69.625)
  line L11 (-50.575, -69.625) -> (-50.575, -75.34)
  line L12 (-50.575, -75.34) -> (-6.575, -75.34)
  line L13 (-6.575, -75.34) -> (-6.575, -67.72)
  line L14 (-6.575, -67.72) -> (12.475, -67.72)
  line L15 (12.475, -67.72) -> (12.475, -58.195)
  line L16 (12.475, -58.195) -> (88.675, -58.195)
  line L17 (88.675, -58.195) -> (88.675, -35.72)
  line L18 (88.675, -35.72) -> (76.2, -35.72)
  line L19 (76.2, -45.72) -> (66.2, -45.72) construction
  line L20 (66.2, -45.72) -> (66.2, -58.195) construction
  line L21 (12.475, -58.195) -> (0, -45.72) construction
  line L22 (6.2375, -51.9575) -> (66.2, -51.9575) construction
  line L23 (-28.575, -75.34) -> (-28.575, -62.865) construction
  circle A2 centre (-28.575, -69.1025) radius 1.275
  circle A3 centre (36.2188, -51.9575) radius 1.275
  line L24 (-84.085, -57.15) -> (-84.085, -47.15)
  dimension "d214" = 10
  dimension "d215" = 2.55
  dimension "d216" = 2.55
  constraint coincident L0.end L1.start
  constraint perpendicular L0 L19
  constraint coincident L16 L20.end
  constraint perpendicular L16 L20
  constraint coincident L15.end L16.start
  constraint coincident L1.end L2.start
  constraint midpoint L21 L22.start
  constraint midpoint L20 L22.end
  constraint midpoint L12 L23.start
  constraint midpoint L5 L23.end
  constraint midpoint L23 A2.centre
  constraint midpoint L22 A3.centre
  measures "d214" distance of L0.end L19.end
  measures "d215" diameter of A2
  measures "d216" diameter of A3
sketch "Sketch10" plane through (0, -12.5, 0) normal (0, -1, 0) x (1, 0, 0)
  circle A0 centre (-76.1479, 119.852) radius 1.025
  circle A1 centre (65.2056, 57.5856) radius 1.025
  line L0 (-71.7017, 112.1511) -> (-8.0926, 95.1071)
  line L1 (-8.0926, 95.1071) -> (-4.6495, 68.58)
  line L2 (-4.6495, 68.58) -> (57.15, 68.58)
  line L3 (57.15, 68.58) -> (57.15, 49.53)
  line L4 (57.15, 49.53) -> (76.2, 49.53)
  line L5 (76.2, 49.53) -> (76.2, 39.53)
  line L6 (76.2, 39.53) -> (88.675, 39.53)
  line L7 (88.675, 39.53) -> (88.675, 62.005)
  line L8 (88.675, 62.005) -> (69.625, 62.005)
  line L9 (69.625, 62.005) -> (69.625, 81.055)
  line L10 (69.625, 81.055) -> (6.3109, 81.055)
  line L11 (6.3109, 81.055) -> (3.2035, 104.9953)
  line L12 (3.2035, 104.9953) -> (-80.5229, 127.4298)
  line L13 (-80.5229, 127.4298) -> (-86.3399, 105.7206)
  line L14 (-86.3399, 105.7206) -> (-74.2899, 102.4918)
  line L15 (-74.2899, 102.4918) -> (-71.7017, 112.1511)
  line L16 (-4.6495, 68.58) -> (6.3109, 81.055) construction
  line L17 (57.15, 68.58) -> (69.625, 81.055) construction
  line L18 (63.3875, 74.8175) -> (0.8307, 74.8175) construction
  circle A2 centre (32.1091, 74.8175) radius 1.275
  line L19 (-8.0926, 95.1071) -> (3.2035, 104.9953) construction
  line L20 (-6.3711, 81.8435) -> (4.7572, 93.0252) construction
  line L21 (-8.0926, 95.1071) -> (-37.0704, 102.8716) construction
  line L22 (-37.0704, 102.8716) -> (-33.8417, 114.9216) construction
  line L23 (-35.456, 108.8966) -> (-0.8069, 87.4344) construction
  line L24 (-18.1315, 98.1655) -> (3.2035, 104.9953) construction
  line L25 (-7.464, 101.5804) -> (-2.4446, 100.0512) construction
  line L26 (-7.464, 101.5804) -> (-4.5285, 98.227) construction
  line L27 (-2.4446, 100.0512) -> (-4.5285, 98.227) construction
  circle A3 centre (-3.4865, 99.1391) radius 1.275
  line L28 (-38.6597, 116.2126) -> (-41.8885, 104.1626) construction
  circle A4 centre (-40.2741, 110.1876) radius 1.275
  dimension "d217" = 2.55
  dimension "d218" = 30
  dimension "d219" = 2.55
  dimension "d221" = 2.55
  constraint coincident L1.end L2.start
  constraint coincident L10.end L11.start
  constraint coincident L2.end L3.start
  constraint coincident L9.end L10.start
  constraint midpoint L17 L18.start
  constraint midpoint L16 L18.end
  constraint midpoint L18 A2.centre
  constraint coincident L0.end L1.start
  constraint coincident L11.end L12.start
  constraint midpoint L1 L20.start
  constraint midpoint L11 L20.end
  constraint coincident L0 L21.end
  constraint coincident L12 L22.end
  constraint perpendicular L12 L22
  constraint midpoint L22 L23.start
  constraint midpoint L20 L23.end
  constraint midpoint L23 L24.start
  constraint midpoint L24 L25.start
  constraint midpoint L19 L25.end
  constraint coincident L19 L26.end
  constraint perpendicular L19 L26
  constraint midpoint L27 A3.centre
  constraint midpoint L12 L28.start
  constraint coincident L0 L28.end
  constraint perpendicular L0 L28
  constraint midpoint L28 A4.centre
  measures "d217" diameter of A2
  measures "d218" distance of L0.end L21.end
  measures "d219" diameter of A3
  measures "d221" diameter of A4
extrude "Extrude16" cut sketch "Sketch10" sketch "Sketch9" against normal blind 5.05 contours A2 | A3 | A4 of sketch 2 contours A2 | A3
fillet "Fillet3" radius 1.275 5 edges at (30.9204, -7.45, 75.2786) (-4.6753, -7.45, 99.6002) (-41.4628, -7.45, 110.6487) (-29.7637, -7.45, -68.6414) (35.03, -7.45, -51.4964)
fillet "Fillet4" radius 2.5 14 edges at (-80.5229, -7.85, 127.4298) (3.2035, -6.25, 104.9953) (6.3109, -6.25, 81.055) (69.625, -7.85, 81.055) (69.625, -7.85, 62.005) (88.675, -7.85, 62.005) (88.675, -7.85, -58.195) (12.475, -6.25, -58.195) (12.475, -6.25, -67.72) (-6.575, -6.25, -67.72) (-6.575, -6.25, -75.34) (-50.575, -6.25, -69.625) (-50.575, -6.25, -75.34) (-96.56, -7.85, -69.625)
fillet "Fillet5" radius 120 2 edges at (-96.56, -12.1987, 60.325) (-94.4114, -12.1471, 75.5973)
equation "sw_size_Ref_Ref = 19.05 mm"
equation "sw_cut_size_Ref_Ref = 14 mm"
equation "sw_cut_space_Ref_Ref = sw_size_Ref_Ref - sw_cut_size_Ref_Ref"
equation "stab_cut_length_Ref_Ref = 6 mm"
equation "stab_cut_height_Ref_Ref = 12.5 mm"
equation "stabw_length_Ref_Ref = 12 mm" comment "Length of the stabilizer wire per unit (e.g. a 2u stabilizer will be stabilizer_wire_length * 2)"
equation "stabw_height_Ref_Ref = 2.5 mm"
equation "stabw_cut_length_Ref_Ref = 1.7 mm"
equation "stabw_cut_height_Ref_Ref = 1 mm"
equation "plt_thickness_Ref_Ref = 1.5 mm"
equation "plt_fillet_Ref_Ref = 0.25 mm"
equation "pcb_thickness_Ref_Ref = 1.6 mm"
equation "m2scr_diameter_Ref_Ref = 2.05 mm"
equation "mtscr_head_diameter_Ref_Ref = 3.5 mm"
equation "mtscr_head_width_Ref_Ref = 0.5 mm"
equation "ctrl_length_Ref_Ref = 33 mm"
equation "ctrl_height_Ref_Ref = 18 mm"
equation "ctrl_width_Ref_Ref = 1.7 mm"
equation "usbc_length_Ref_Ref = 8.34 mm"
equation "usbc_height_Ref_Ref = 2.56 mm"
equation "bat_length_Ref_Ref = 50 mm"
equation "bat_height_Ref_Ref = 34 mm"
equation "bat_width_Ref_Ref = 5 mm"
equation "bat_clearance_Ref_Ref = 3 mm"
equation "key_size_Ref_Ref = 16.5 mm"
equation "key_clearance_Ref_Ref = 0.25 mm"
equation "key_space_Ref_Ref = sw_size_Ref_Ref - ( key_size_Ref_Ref + key_clearance_Ref_Ref )"
equation "key_fillet_Ref_Ref = 1 mm"
equation "thrins_diameter_Ref_Ref = 3.5 mm"
equation "thrins_depth_Ref_Ref = 2.5 mm"
equation "top_inner_thickness_Ref_Ref = 1.5 mm"
equation "plt_up_clearance_Ref_Ref = 4.9 mm"
equation "alignh_diameter_Ref_Ref = 2.5 mm"
equation "alignh_height_Ref_Ref = 5 mm"
equation "case_border_width_Ref_Ref = 10 mm"
equation "col_mid_offset_Ref_Ref = 0.3 * sw_size_Ref_Ref"
equation "col_ring_offset_Ref_Ref = 0.4 * sw_size_Ref_Ref"
equation "col_pinky_offset_Ref_Ref = 0.5 * sw_size_Ref_Ref"
equation "stab_vert_offset_Ref_Ref = 0.6 mm"
equation "stabw_cut_offset_Ref_Ref = 0.835 mm"
equation "plt_border_width_Ref_Ref = 2.475 mm"
equation "case_top_thickness_Ref_Ref = 4 mm"
equation "top_align_mark_length_Ref_Ref = 10 mm"
equation "pcb_clearance_Ref_Ref = 8.5 mm"
equation "case_bot_min_thickness_Ref_Ref = 3 mm"
equation "case_max_length_Ref_Ref = max(7 * sw_size_Ref_Ref + plt_border_width_Ref_Ref * 2 + case_border_width_Ref_Ref * 2; 8 * sw_size_Ref_Ref + ( plt_border_width_Ref_Ref + case_border_width_Ref_Ref ) * 2 + 7.885 mm)"
equation "case_bot_angle_Ref_Ref = 2.75 deg"
equation "case_bot_max_thickness_Ref_Ref = case_max_length_Ref_Ref / tan(90 deg - case_bot_angle_Ref_Ref) + case_bot_min_thickness_Ref_Ref"
equation "ctrl_socket_height_Ref_Ref = 4.191 mm"
equation "bat_wall_thickness_Ref_Ref = 2.5 mm"
equation "bat_offset_Ref_Ref = 25 mm + bat_wall_thickness_Ref_Ref + bat_length_Ref_Ref * 0.5"
equation "sw_hotswap_clearance_Ref_Ref = 1.9 mm"
equation "case_side_fillet_Ref_Ref = 2.5 mm"
equation "case_top_fillet_Ref_Ref = 0.5 mm"
equation "case_top_inner_border_side_fillet_Ref_Ref = 1.5 mm"
equation "case_top_inner_border_top_fillet_Ref_Ref = 1 mm"
equation "usbc_contour_height_Ref_Ref = 4.5 mm"
equation "usbc_contour_length_Ref_Ref = 12 mm"
equation "assemblyscr_head_diameter_Ref_Ref = 4.15 mm"
equation "assemblyscr_head_width_Ref_Ref = 0.85 mm"